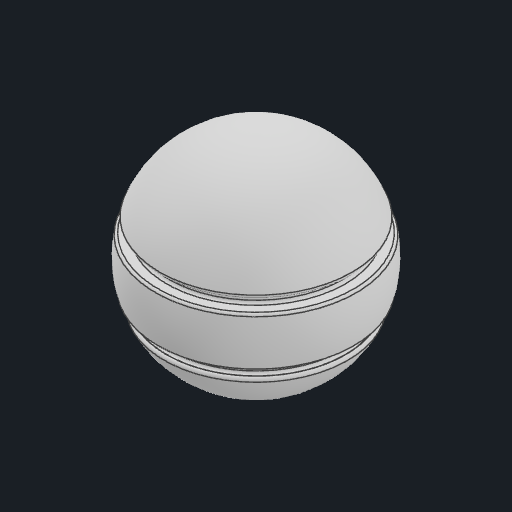
# Autodesk Inventor part: ball-grooves
Saved by Autodesk Inventor 2026.1 (Build 301233000, 233)
## iProperties
Created: 2026-11-04
Part Number: ball-grooves
Material: Generic
Document SubType Name: Modeling
Designer: anony
Density: 1 g/cm^3
Appearance: Default
Author: anony
Autodesk Inventor part; units mm, degrees
ref_plane "YZ Plane" through (0, 0, 0) normal (1, 0, 0) x (0, 1, 0)
ref_plane "XZ Plane" through (0, 0, 0) normal (0, 1, 0) x (-1, 0, 0)
ref_plane "XY Plane" through (0, 0, 0) normal (0, 0, 1) x (1, 0, 0)
sketch "Sketch1" plane through (0, 0, 0) normal (0, 0, 1) x (1, 0, 0)
  arc A0 (0, -10) -> (0, 10) centre (0, 0) ccw
  line L0 (0, 10) -> (0, -10)
  line L1 (0, -14) -> (0, 14)
  constraints: 2 end point, 2 point on circle, 1 centre point
revolve "Revolution1" add sketch "Sketch1" angle 360 about axis through (0, -10, 0) along (0, 1, 0)
sketch "Sketch2" plane through (0, 0, 0) normal (0, 0, 1) x (1, 0, 0)
  line L0 (8.5, 2) -> (11, 2)
  line L1 (11, 2) -> (11, 3)
  line L2 (11, 3) -> (8.5, 3)
  line L3 (8.5, 3) -> (8.5, 2)
  line L4 (8.5, -4) -> (11, -4)
  line L5 (11, -4) -> (11, -3)
  line L6 (11, -3) -> (8.5, -3)
  line L7 (8.5, -3) -> (8.5, -4)
  line L8 (0, -14) -> (0, 14)
  constraints: 16 end point, 4 parallel, 2 horizontal, 2 perpendicular
revolve "Revolution2" cut sketch "Sketch2" angle 360 about axis through (0, -10, 0) along (0, 1, 0)
fillet "Fillet1" radius 0.25 8 edges at (-8.5, 2, 0) (-8.5, 3, 0) (-9.5394, 3, 0) (-9.798, 2, 0) (-8.5, -4, 0) (-8.5, -3, 0) (-9.5394, -3, 0) (-9.1652, -4, 0)
body "Solid1"
